intake-plate (Autodesk Fusion 360 design; units mm, degrees)
part number: 2026-11-27-21-02-50-223
Autodesk Fusion 360 part; units mm, degrees
sketch "Sketch1" plane through (0, 0, 0) normal (0, 1, 0) x (1, 0, 0)
sketch "Sketch2" plane through (0, 0, 0) normal (0, 0, 1) x (1, 0, 0)
  line L0 (70, 70) -> (-70, 70)
  line L1 (-70, 70) -> (-70, -70)
  line L2 (-70, -70) -> (70, -70)
  line L3 (70, -70) -> (70, 70)
  line L4 (70, 70) -> (-70, -70) construction
  line L5 (-70, 70) -> (70, -70) construction
  dimension "d1" = 140
  dimension "d2" = 140
  constraint horizontal L0
  constraint perpendicular L0 L1
  constraint parallel L0 L2
  constraint parallel L1 L3
  constraint coincident L4 origin
  constraint coincident L5 origin
  measures "d1" distance of L1.end L2.end
  measures "d2" distance of L0.end L1.end
extrude "Extrude1" add sketch "Sketch2" along normal blind 3
sketch "Sketch3" plane through (0, 0, 3) normal (0, 0, 1) x (1, 0, 0)
  line L0 (70, -70) -> (70, 70)
  line L1 (70, 70) -> (-70, 70)
  line L2 (-70, 70) -> (-70, -70)
  line L3 (-70, -70) -> (70, -70)
  line L4 (-55, 58) -> (-5, 58)
  line L5 (-5, 58) -> (-5, 46)
  line L6 (-5, 46) -> (-55, 46)
  line L7 (-55, 46) -> (-55, 58)
  line L8 (55, 58) -> (55, 46)
  line L9 (5, 58) -> (55, 58)
  line L10 (5, 46) -> (5, 58)
  line L11 (55, 46) -> (5, 46)
  line L12 (-5, 43) -> (-5, 31)
  line L13 (-55, 43) -> (-5, 43)
  line L14 (-55, 31) -> (-55, 43)
  line L15 (-5, 31) -> (-55, 31)
  line L16 (55, 43) -> (55, 31)
  line L17 (5, 43) -> (55, 43)
  line L18 (5, 31) -> (5, 43)
  line L19 (55, 31) -> (5, 31)
  line L20 (-5, 28) -> (-5, 16)
  line L21 (-55, 28) -> (-5, 28)
  line L22 (-55, 16) -> (-55, 28)
  line L23 (-5, 16) -> (-55, 16)
  line L24 (55, 28) -> (55, 16)
  line L25 (5, 28) -> (55, 28)
  line L26 (5, 16) -> (5, 28)
  line L27 (55, 16) -> (5, 16)
  line L28 (-5, 13) -> (-5, 1)
  line L29 (-55, 13) -> (-5, 13)
  line L30 (-55, 1) -> (-55, 13)
  line L31 (-5, 1) -> (-55, 1)
  line L32 (55, 13) -> (55, 1)
  line L33 (5, 13) -> (55, 13)
  line L34 (5, 1) -> (5, 13)
  line L35 (55, 1) -> (5, 1)
  line L36 (-5, -2) -> (-5, -14)
  line L37 (-55, -2) -> (-5, -2)
  line L38 (-55, -14) -> (-55, -2)
  line L39 (-5, -14) -> (-55, -14)
  line L40 (55, -2) -> (55, -14)
  line L41 (5, -2) -> (55, -2)
  line L42 (5, -14) -> (5, -2)
  line L43 (55, -14) -> (5, -14)
  line L44 (-5, -17) -> (-5, -29)
  line L45 (-55, -17) -> (-5, -17)
  line L46 (-55, -29) -> (-55, -17)
  line L47 (-5, -29) -> (-55, -29)
  line L48 (55, -17) -> (55, -29)
  line L49 (5, -17) -> (55, -17)
  line L50 (5, -29) -> (5, -17)
  line L51 (55, -29) -> (5, -29)
  line L52 (-5, -32) -> (-5, -44)
  line L53 (-55, -32) -> (-5, -32)
  line L54 (-55, -44) -> (-55, -32)
  line L55 (-5, -44) -> (-55, -44)
  line L56 (55, -32) -> (55, -44)
  line L57 (5, -32) -> (55, -32)
  line L58 (5, -44) -> (5, -32)
  line L59 (55, -44) -> (5, -44)
  line L60 (-5, -47) -> (-5, -59)
  line L61 (-55, -47) -> (-5, -47)
  line L62 (-55, -59) -> (-55, -47)
  line L63 (-5, -59) -> (-55, -59)
  line L64 (55, -47) -> (55, -59)
  line L65 (5, -47) -> (55, -47)
  line L66 (5, -59) -> (5, -47)
  line L67 (55, -59) -> (5, -59)
  dimension "d5" = 50
  dimension "d6" = 12
  dimension "d7" = 15
  dimension "d8" = 12
  dimension "d11" = 60
  dimension "d12" = -15
  constraint horizontal L4
  constraint vertical L5
  constraint horizontal L6
  constraint vertical L7
  measures "d5" distance of L4.start L4.end
  measures "d6" distance of L4.start L6.end
  measures "d7" distance of L2 L7
  measures "d8" distance of L1 L4
extrude "Extrude2" cut sketch "Sketch3" against normal through all contours L4 L5 L6 L7 | L8 L9 L10 L11 | L12 L13 L14 L15 | L16 L17 L18 L19 | L20 L21 L22 L23 | L24 L25 L26 L27 | L28 L29 L30 L31 | L32 L33 L34 L35 | L36 L37 L38 L39 | L40 L41 L42 L43 | L44 L45 L46 L47 | L48 L49 L50 L51 | L52 L53 L54 L55 | L56 L57 L58 L59 | L60 L61 L62 L63 | L64 L65 L66 L67
